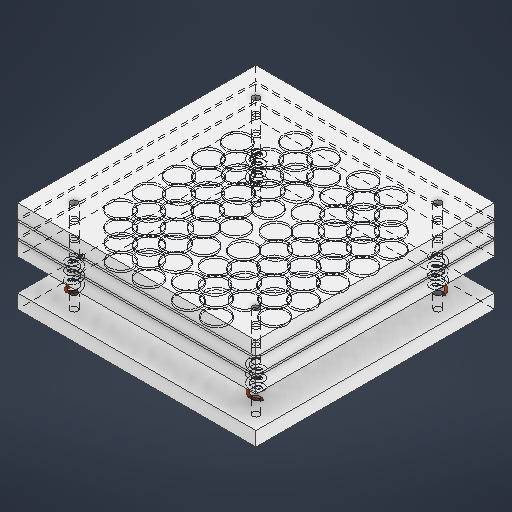
# Autodesk Inventor part: Part2
Saved by Autodesk Inventor 2026 (Build 300175000, 175)
## iProperties
Created: 2025-12-18
Part Number: Part2
Material: Generic
Document SubType Name: Modeling
Designer: MSI NOTEBOOK
Density: 1 g/cm^3
Appearance: Default
Author: MSI NOTEBOOK
Autodesk Inventor part; units mm, degrees
sketch "Sketch1" plane through (0, 0, 0) normal (0, 1, 0) x (-1, 0, 0)
  line L0 (149.86, 149.86) -> (-149.86, 149.86)
  line L1 (-149.86, 149.86) -> (-149.86, -149.86)
  line L2 (-149.86, -149.86) -> (149.86, -149.86)
  line L3 (149.86, -149.86) -> (149.86, 149.86)
  line L4 (149.86, 149.86) -> (-149.86, -149.86) construction
  line L5 (-149.86, 149.86) -> (149.86, -149.86) construction
  point P0 (0, 0)
  dimension "d0" = 299.72
  dimension "d1" = 299.72
  constraints: 12 end point, 2 midpoint, 2 parallel, 1 horizontal, 1 perpendicular
  measures "d0" distance of L1.end L2.end
  measures "d1" distance of L0.end L1.end
extrude "Extrusion1" add sketch "Sketch1" along normal blind 17.78
sketch "Sketch2" plane through (0, 17.78, 0) normal (0, 1, 0) x (1, 0, 0)
  line L0 (-149.86, -149.86) -> (149.86, -149.86) projected
  line L1 (111.76, -149.86) -> (111.76, -114.5785)
  line L2 (114.5785, -111.76) -> (149.86, -111.76)
  line L3 (149.86, -149.86) -> (149.86, 149.86) projected
  circle A0 centre (113.1264, -113.1264) radius 1.9939
  line L4 (0, -149.86) -> (0, 0)
  line L5 (0, 0) -> (149.86, 0)
  circle A1 centre (-113.1264, -113.1264) radius 1.9939
  circle A2 centre (113.1264, 113.1264) radius 1.9939
  line L6 (0, 0) -> (0, 149.86)
  line L7 (149.86, 149.86) -> (-149.86, 149.86) projected
  circle A3 centre (-113.1264, 113.1264) radius 1.9939
  dimension "d4" = 38.1
  dimension "d5" = 38.1
  dimension "d6" = 3.9878
  constraints: 10 end point, 4 centre point, 3 midpoint, 3 symmetric about line, 2 point on circle, 2 point on line, 2 vertical, 1 perpendicular, 3 other
  measures "d4" distance of L0.end L1.start
  measures "d5" distance of L2.end L0.end
  measures "d6" diameter of A0
extrude "Extrusion2" cut sketch "Sketch2" along normal through all both and the other way through all contours A0
mirror "Mirror1" about plane through (0, 0, 0) normal (1, 0, 0) of "Extrusion2"
mirror "Mirror2" about plane through (0, 0, 0) normal (0, 0, 1) of "Extrusion2", "Mirror1"
sketch "Sketch4" plane through (0, 17.78, 0) normal (0, 1, 0) x (1, 0, 0)
  circle A0 centre (24.892, -109.8042) radius 14.986
  line L0 (-149.86, -149.86) -> (149.86, -149.86) projected
  circle A1 centre (60.0564, -109.8042) radius 14.986
  circle A2 centre (60.2653, -74.2155) radius 14.986
  circle A3 centre (24.892, -76.2799) radius 14.986
  circle A4 centre (24.892, -40.4631) radius 14.986
  circle A5 centre (60.6561, -38.5012) radius 14.986
  circle A6 centre (97.0889, -37.464) radius 14.986
  circle A7 centre (96.7389, -73.3369) radius 14.986
  circle A8 centre (25.2095, 0) radius 14.986
  circle A9 centre (60.6561, 0) radius 14.986
  circle A10 centre (96.7389, 0) radius 14.986
  point P0 (0, 0)
  point P1 (0, -149.86)
  dimension "d9" = 29.972
  dimension "d11" = 40.0558
  dimension "d13" = 24.892
  dimension "d16" = 29.972
  dimension "d17" = 29.972
  dimension "d18" = 29.972
  dimension "d19" = 29.972
  dimension "d20" = 29.972
  dimension "d21" = 29.972
  dimension "d22" = 29.972
  dimension "d23" = 29.972
  dimension "d24" = 29.972
  dimension "d25" = 29.972
  constraints: 11 centre point, 1 midpoint
  measures "d9" diameter of A0
  measures "d11" distance from line of L0 A0.centre
  measures "d13" horizontal distance of A0.centre point (0, -149.86)
  measures "d16" diameter of A1
  measures "d17" diameter of A2
  measures "d18" diameter of A3
  measures "d19" diameter of A4
  measures "d20" diameter of A5
  measures "d21" diameter of A6
  measures "d22" diameter of A7
  measures "d23" diameter of A8
  measures "d24" diameter of A9
  measures "d25" diameter of A10
extrude "Extrusion3" add sketch "Sketch4" along normal blind 2.54
mirror "Mirror3" about plane through (0, 0, 0) normal (0, 0, 1) of "Extrusion3"
mirror "Mirror4" about plane through (0, 0, 0) normal (1, 0, 0) of "Extrusion3", "Extrusion1", "Mirror3"
sketch "Sketch7" plane through (0, 17.78, 0) normal (0, 1, 0) x (1, 0, 0)
  circle A0 centre (114.3, -114.3) radius 4.445
  line L0 (-149.86, -149.86) -> (149.86, -149.86) projected
  line L1 (149.86, -149.86) -> (149.86, 149.86) projected
  point P0 (0, 0)
  dimension "d26" = 8.89
  dimension "d27" = 35.56
  dimension "d28" = 35.56
  constraints: 1 centre point
  measures "d26" diameter of A0
  measures "d27" distance from line of L0 A0.centre
  measures "d28" distance from line of L1 A0.centre
extrude "Extrusion4" cut sketch "Sketch7" against normal through all
mirror "Mirror5" about plane through (0, 0, 0) normal (1, 0, 0) of "Extrusion4"
mirror "Mirror6" about plane through (0, 0, 0) normal (0, 0, 1) of "Extrusion4", "Mirror5"
ref_plane "Work Plane1" through (-25.2095, 19.05, 0) normal (0, 1, 0) x (1, 0, 0)
mirror "Mirror7" about plane through (-25.2095, 19.05, 0) normal (0, 1, 0) of "Extrusion1", "Extrusion4", "Mirror5", "Mirror6"
ref_plane "Work Plane2" through (-149.86, 29.21, -149.86) normal (0, 1, 0) x (1, 0, 0)
mirror "Mirror8" about plane through (-149.86, 29.21, -149.86) normal (0, 1, 0) of "Extrusion3", "Mirror3", "Extrusion1", "Mirror4"
mirror "Mirror9" about plane through (-149.86, 29.21, -149.86) normal (0, 1, 0) of "Extrusion4", "Mirror5", "Mirror6"
ref_plane "Work Plane3" through (0, -19.812, 0) normal (0, -1, 0) x (1, 0, 0)
mirror "Mirror10" about plane through (0, -19.812, 0) normal (0, -1, 0) of "Extrusion1", "Extrusion4", "Mirror5", "Mirror6"
sketch "Sketch10" plane through (0, 0, 0) normal (0, -1, 0) x (1, 0, 0)
  point P0 (0, 0)
ref_plane "Work Plane4" through (-149.86, -39.624, 114.3) normal (0, 0, 1) x (1, 0, 0)
ref_plane "Work Plane5" through (149.86, -39.624, -114.3) normal (0, 0, -1) x (-1, 0, 0)
sketch "Sketch11" plane through (-149.86, -39.624, 114.3) normal (0, 0, 1) x (1, 0, 0)
  line L0 (299.72, 0) -> (0, 0) projected
  line L1 (35.5518, 0) -> (35.56, 39.624)
  line L2 (40.005, 39.624) -> (31.115, 39.624) projected
  circle A0 centre (27.9324, 2.54) radius 1.7573
  point P0 (149.86, 39.624)
  dimension "d34" = 2.54
  dimension "d43" = 7.62
  constraints: 2 end point, 1 centre point, 1 midpoint, 1 point on line
  measures "d34" distance from line of L0 A0.centre
  measures "d43" distance from line of A0.centre L1
coil "Coil1" sketch "Sketch11" operation add axis through (-114.3082, -39.624, 114.3) along (0.0002, 1, 0) pitch 10.16 turns 3.7 hand right
mirror "Mirror11" about plane through (0, 0, 0) normal (1, 0, 0) of "Coil1"
mirror "Mirror12" about plane through (0, 0, 0) normal (0, 0, 1) of "Coil1", "Mirror11"
body "Solid1"
